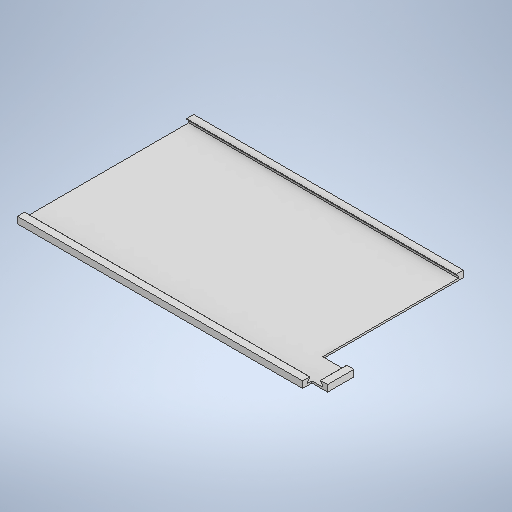
# Autodesk Inventor part: Screen_holder
Saved by Autodesk Inventor 2025.2 (Build 292293000, 293)
## iProperties
Created: 2026-07-17
Part Number: Screen_holder
Material: Generic
Document SubType Name: Modeling
Designer: Bruno
Density: 1 g/cm^3
Appearance: Default
Author: Bruno
## iProperties of the stored document Screen_holder_3DPrint.ipt
Created: 2026-07-17
Part Number: Screen_holder_3DPrint
Material: Generic
Document SubType Name: Modeling
Designer: Bruno
Density: 1 g/cm^3
Appearance: Default
Author: Bruno
Autodesk Inventor part; units mm, degrees
ref_plane "YZ Plane" through (0, 0, 0) normal (1, 0, 0) x (0, 1, 0)
ref_plane "XZ Plane" through (0, 0, 0) normal (0, 1, 0) x (-1, 0, 0)
ref_plane "XY Plane" through (0, 0, 0) normal (0, 0, 1) x (1, 0, 0)
sketch "Sketch1" plane through (0, 0, 0) normal (0, 1, 0) x (-1, 0, 0)
  line L0 (46.5, 26.6) -> (-46.5, 26.6) construction
  line L1 (-46.5, 26.6) -> (-46.5, -26.6) construction
  line L2 (-46.5, -26.6) -> (46.5, -26.6) construction
  line L3 (46.5, -26.6) -> (46.5, 26.6) construction
  line L4 (46.5, 26.6) -> (-46.5, -26.6) construction
  line L5 (-46.5, 26.6) -> (46.5, -26.6) construction
  line L6 (-48.1, 28.2) -> (48.1, 28.2)
  line L7 (48.1, 28.2) -> (48.1, -28.2)
  line L8 (48.1, -28.2) -> (-48.1, -28.2)
  line L9 (-48.1, -28.2) -> (-48.1, 28.2)
  point P0 (0, 0)
  dimension "d0" = 53.2
  dimension "d1" = 93
  dimension "d2" = 1.6
  constraints: 20 end point, 4 parallel, 2 midpoint, 2 perpendicular, 1 horizontal, 3 other
  measures "d0" distance between parallel lines of L0 L2
  measures "d1" distance between parallel lines of L1 L3
  measures "d2" distance between parallel lines of L0 L6
extrude "Extrusion1" add sketch "Sketch1" along normal blind 0.6
sketch "Sketch2" plane through (0, 0.6, 0) normal (0, 1, 0) x (1, 0, 0)
  line L0 (48.1, 28.2) -> (-48.1, 28.2) projected
  line L1 (-48.1, 28.2) -> (-48.1, -28.2) projected
  line L2 (-48.1, -28.2) -> (48.1, -28.2) projected
  line L3 (48.1, -28.2) -> (48.1, 28.2) projected
  line L4 (46.5, -26.6) -> (-46.5, -26.6)
  line L5 (-46.5, -26.6) -> (-46.5, 26.6)
  line L6 (-46.5, 26.6) -> (46.5, 26.6)
  line L7 (46.5, 26.6) -> (46.5, -26.6)
  line L8 (-46.5, -26.6) -> (-48.1, -26.6)
  line L9 (-46.5, 26.6) -> (-48.1, 26.6)
  point P0 (0, 0)
  dimension "d5" = 1.6
  constraints: 12 end point, 2 perpendicular, 2 point on line, 3 other
  measures "d5" distance between parallel lines of L2 L4
extrude "Extrusion2" add sketch "Sketch2" along normal blind 1.3 contours L3 L2 L1 L8 L4 L7 L6 L9 L0
sketch "Sketch3" plane through (0, 1.9, 0) normal (0, 1, 0) x (1, 0, 0)
  line L0 (46.5, -26.6) -> (-48.1, -26.6) projected
  line L1 (-48.1, 26.6) -> (46.5, 26.6) projected
  line L2 (46.5, 26.6) -> (46.5, -26.6) projected
  line L3 (-48.1, -25.9) -> (45.8, -25.9)
  line L4 (45.8, -25.9) -> (45.8, 25.9)
  line L5 (45.8, 25.9) -> (-48.1, 25.9)
  line L6 (-48.1, 26.6) -> (-48.1, -26.6) projected
  line L7 (-48.1, 28.2) -> (-48.1, 26.6) projected
  line L8 (-48.1, 26.6) -> (46.5, 26.6) projected
  line L9 (46.5, 26.6) -> (46.5, -26.6) projected
  line L10 (46.5, -26.6) -> (-48.1, -26.6) projected
  line L11 (-48.1, -26.6) -> (-48.1, -28.2) projected
  line L12 (-48.1, -28.2) -> (48.1, -28.2) projected
  line L13 (48.1, -28.2) -> (48.1, 28.2) projected
  line L14 (48.1, 28.2) -> (-48.1, 28.2) projected
  point P0 (0, 0)
  point P1 (-48.1, -26.6)
  dimension "d8" = 0.7
  constraints: 6 end point, 2 other
  measures "d8" distance between parallel lines of L0 L3
extrude "Extrusion3" add sketch "Sketch3" along normal blind 0.2 contours L2 L1 L7 L14 L13 L12 L11 L0 | L0 L6 L3 L4 L5 L1 L2
chamfer "Chamfer1" distance 0.7 angle 45 3 edges at (-0.8, 1.9, 26.6) (46.5, 1.9, 0) (-0.8, 1.9, -26.6)
sketch "Sketch4" plane through (0, 2.1, 0) normal (0, 1, 0) x (1, 0, 0)
  line L0 (48.1, 28.2) -> (-48.1, 28.2) projected
  line L1 (48.1, -28.2) -> (48.1, 28.2) projected
  line L2 (-48.1, -28.2) -> (48.1, -28.2) projected
  line L3 (-48.1, 28.2) -> (-48.1, -28.2) projected
  line L4 (38.1, -16.8) -> (48.1, -16.8)
  line L5 (48.1, -16.8) -> (48.1, 28.2)
  line L6 (48.1, 28.2) -> (38.1, 28.2)
  line L7 (38.1, 28.2) -> (38.1, -16.8)
  line L8 (48.1, -28.2) -> (43.1, -28.2)
  line L9 (43.1, -28.2) -> (43.1, -25.2)
  line L10 (43.1, -25.2) -> (48.1, -25.2)
  line L11 (48.1, -25.2) -> (48.1, -28.2)
  dimension "d18" = 3
  dimension "d19" = 5
  dimension "d20" = 10
  dimension "d21" = 45
  constraints: 16 end point, 4 parallel, 2 horizontal, 2 perpendicular
  measures "d18" distance of L8.end L9.end
  measures "d19" distance of L9.end L10.end
  measures "d20" distance of L4.start L4.end
  measures "d21" distance of L6.end L4.start
extrude "Extrusion4" cut sketch "Sketch4" against normal through all contours L1 L4 L7 L0 | L1 L2 L9 L10
body "Solid1"
